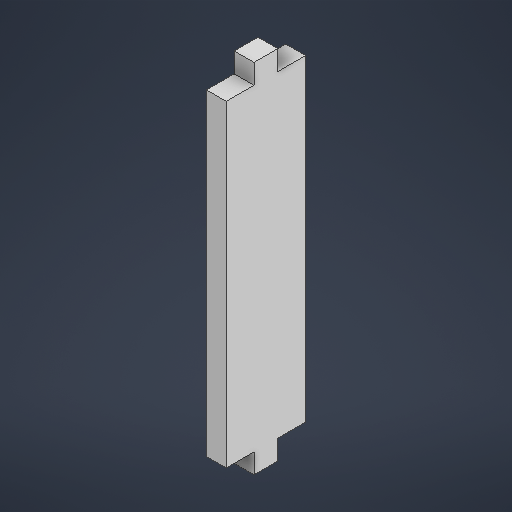
# Autodesk Inventor part: Pared_Lado
Saved by Autodesk Inventor 2025.2 (Build 292293000, 293)
## iProperties
Created: 2025-06-04
Part Number: Pared_Lado
Material: Genérico
Document SubType Name: Modeling
Designer: Niko
Density: 1 g/cm^3
Appearance: Valor por defecto
Author: Niko
Autodesk Inventor part; units mm, degrees
ref_plane "YZ Plane" through (0, 0, 0) normal (1, 0, 0) x (0, 1, 0)
ref_plane "XZ Plane" through (0, 0, 0) normal (0, 1, 0) x (-1, 0, 0)
ref_plane "XY Plane" through (0, 0, 0) normal (0, 0, 1) x (1, 0, 0)
sketch "Boceto1" plane through (0, 0, 0) normal (1, 0, 0) x (0, 1, 0)
  line L0 (40, 10) -> (0, 10)
  line L1 (45, 3) -> (45, 0)
  line L2 (45, 3) -> (40, 3)
  line L3 (40, 3) -> (40, 10)
  line L4 (40, -10) -> (0, -10)
  line L5 (45, -3) -> (45, 0)
  line L6 (45, -3) -> (40, -3)
  line L7 (40, -3) -> (40, -10)
  line L8 (-40, 10) -> (0, 10)
  line L9 (-45, 3) -> (-45, 0)
  line L10 (-45, 3) -> (-40, 3)
  line L11 (-40, 3) -> (-40, 10)
  line L12 (-40, -10) -> (0, -10)
  line L13 (-45, -3) -> (-40, -3)
  line L14 (-40, -3) -> (-40, -10)
  line L15 (-45, -3) -> (-45, 0)
  point P0 (0, 0)
  constraints: 32 end point, 1 horizontal, 1 vertical
extrude "Extrusión2" add sketch "Boceto1" along normal blind 5
